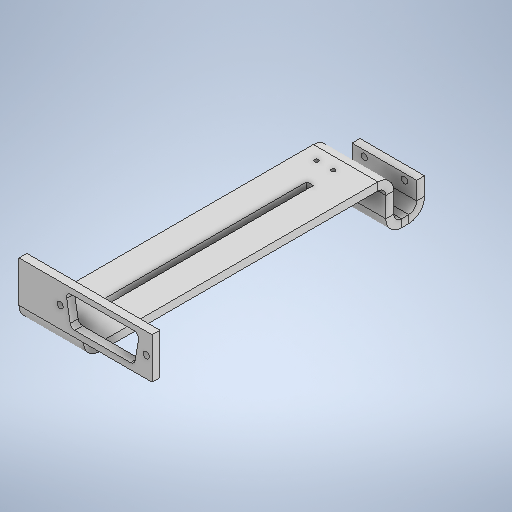
# Autodesk Inventor part: Blacha
Saved by Autodesk Inventor 2025.2 (Build 292293000, 293)
## iProperties
Created: 2025-04-10
Part Number: Blacha
Material: Generic
Document SubType Name: Sheet Metal
Designer: makst
Density: 1 g/cm^3
Sheet Metal Rule: Default
Appearance: Default
Author: makst
Autodesk Inventor part; units mm, degrees
ref_plane "YZ Plane" through (0, 0, 0) normal (1, 0, 0) x (0, 1, 0)
ref_plane "XZ Plane" through (0, 0, 0) normal (0, 1, 0) x (-1, 0, 0)
ref_plane "XY Plane" through (0, 0, 0) normal (0, 0, 1) x (1, 0, 0)
sketch "Sketch1" plane through (0, 0, 0) normal (0, 1, 0) x (-1, 0, 0)
  line L0 (0, 0) -> (0, -15)
  line L1 (0, -15) -> (25, -15)
  line L2 (25, -15) -> (25, 0)
  line L3 (25, 0) -> (0, 0)
  dimension "d0" = 15
  dimension "d2" = 25
  measures "d0" distance of L0.start L0.end
  measures "d2" distance of L0.end L1.end
extrude "Plate1" add sketch "Sketch1" along normal blind 3.048
sketch "Sketch2" plane through (-25, 0, -11.952) normal (0, 0, -1) x (-1, 0, 0)
  line L0 (-25, 0) -> (0, 0)
  line L1 (0, 0) -> (0, 23)
  line L2 (0, 23) -> (-25, 23)
  line L3 (-25, 23) -> (-25, 0)
  constraints: 6 end point, 1 horizontal, 1 perpendicular, 1 vertical
edge flange "Flange1" height 23 angle 90 thickness 3.048 bend radius 3.048 thickness toward (0, 0, -1) relief tear relief width 3.048 relief depth 1.524 edges at (-12.5, 3.048, -15) wall of the first edge with corners at (0, 0, -11.952) (-25, 0, -11.952) (-25, 23, -11.952) (0, 23, -11.952)
bend "Bend1"
corner "Corner1"
sketch "Sketch4" plane through (0, 23, -15) normal (0, 0, -1) x (-1, 0, 0)
  line L0 (0, -16.904) -> (25, -16.904) projected
  line L1 (0, -16.904) -> (0, 0) projected
  line L2 (25, 0) -> (25, -16.904) projected
  line L3 (12.5, -16.904) -> (12.5, -5.7009) construction
  point P0 (0, -23)
  point P1 (4.73, -12.2858)
  point P2 (20.27, -12.2858)
  dimension "d14" = 7.77
  dimension "d15" = 7.77
  constraints: 2 end point, 1 midpoint, 1 vertical
  measures "d14" distance from line of L3 point (4.73, -12.286)
  measures "d15" distance from line of point (20.27, -12.286) L3
hole "Hole1" at (-4.73, 10.7142, -15) at (-20.27, 10.7142, -15) direction (0, 0, 1) diameter 2.459 depth 4 thread size "M3x0.5" class "6H" standard "ISO Metric profile"
sketch "Sketch5" plane through (-25, 23, -11.952) normal (0, 0, 1) x (1, 0, 0)
  line L0 (25, 0) -> (0, 0) projected
  line L1 (0, 0) -> (0, -10)
  line L2 (0, 0) -> (0, -16.904) projected
  line L3 (0, -10) -> (25, -10)
  line L4 (25, -16.904) -> (25, 0) projected
  line L5 (25, 0) -> (0, 0)
  point P0 (25, -23)
  dimension "d23" = 10
  constraints: 6 end point, 2 point on line, 1 parallel, 1 perpendicular
  measures "d23" distance of L0.end L1.end
extrude "Extrusion1" cut sketch "Sketch5" against normal blind 10
sketch "Sketch7" plane through (0, 0, -3.048) normal (0, 0, 1) x (1, 0, 0)
  line L0 (-25, 0) -> (0, 0)
  line L1 (0, 0) -> (0, 20)
  line L2 (0, 20) -> (-25, 20)
  line L3 (-25, 20) -> (-25, 0)
  constraints: 6 end point, 1 horizontal, 1 perpendicular, 1 vertical
edge flange "Flange2" height 20 angle 90 thickness 3.048 bend radius 3.048 thickness toward (0, 0, 1) relief tear relief width 3.048 relief depth 1.524 edges at (-12.5, 3.048, 0) wall of the first edge with corners at (-25, 0, -3.048) (0, 0, -3.048) (0, 20, -3.048) (-25, 20, -3.048)
bend "Bend2"
corner "Corner2"
sketch "Sketch8" plane through (-25, 16.952, -3.048) normal (0, 1, 0) x (-1, 0, 0)
  line L0 (-25, 0) -> (0, 0)
  line L1 (0, 0) -> (0, 120)
  line L2 (0, 120) -> (-25, 120)
  line L3 (-25, 120) -> (-25, 0)
  constraints: 6 end point, 1 horizontal, 1 perpendicular, 1 vertical
edge flange "Flange3" height 120 angle 90 thickness 3.048 bend radius 3.048 thickness toward (0, 1, 0) relief tear relief width 3.048 relief depth 1.524 edges at (-12.5, 20, 0) wall of the first edge with corners at (0, 16.952, -3.048) (-25, 16.952, -3.048) (-25, 16.952, 116.952) (0, 16.952, 116.952)
bend "Bend3"
corner "Corner3"
sketch "Sketch9" plane through (-25, 20, 116.952) normal (0, 1, 0) x (1, 0, 0)
  line L0 (25, 113.904) -> (25, 0) projected
  line L1 (0, 0) -> (0, 113.904) projected
  line L2 (25, 0) -> (0, 0) projected
  line L3 (25, 113.904) -> (0, 113.904) projected
  line L4 (0, 113.904) -> (25, 113.904) projected
  line L5 (11.25, 18.904) -> (11.25, 98.904)
  line L6 (13.75, 18.904) -> (13.75, 98.904)
  line L7 (12.5, 98.904) -> (12.5, 97.654)
  line L8 (11.25, 18.904) -> (11.25, 17.654)
  line L9 (11.25, 17.654) -> (13.75, 17.654)
  line L10 (13.75, 17.654) -> (13.75, 18.904)
  line L11 (11.25, 98.904) -> (11.25, 100.154)
  line L12 (11.25, 100.154) -> (13.75, 100.154)
  line L13 (13.75, 100.154) -> (13.75, 98.904)
  point P0 (25, 116.952)
  dimension "d46" = 15
  constraints: 18 end point, 3 perpendicular, 1 coincident, 1 point on line, 1 vertical
  measures "d46" distance from line of L3 point (12.5, 98.904)
extrude "Extrusion2" cut sketch "Sketch9" against normal blind 10 contours L5 L11 L12 L13 L6 L10 L9 L8
sketch "Sketch10" plane through (-25, 16.952, 116.952) normal (0, -1, 0) x (1, 0, 0)
  line L0 (0, -113.904) -> (0, 0) projected
  line L1 (13.75, -100.154) -> (11.25, -100.154) projected
  line L2 (13.75, -100.154) -> (13.75, -58.904) construction
  line L3 (13.75, -100.154) -> (13.75, -17.654) projected
  line L4 (13.75, -58.904) -> (32.0073, -58.904) construction
  point P0 (25, -116.952)
  point P1 (12.5, -109.154)
  point P2 (6, -109.154)
  point P3 (12.5, -8.654)
  point P4 (6, -8.654)
  dimension "d52" = 12.5
  dimension "d53" = 9
  dimension "d54" = 6.5
  dimension "d62" = 41.25
  constraints: 4 end point, 2 symmetric about line, 1 horizontal, 1 midpoint
  measures "d52" distance from line of point (12.5, -109.154) L0
  measures "d53" distance from line of point (12.5, -109.154) L1
  measures "d54" distance of point (6, -109.154) point (12.5, -109.154)
  measures "d62" distance of L1.start L2.end
hole "Hole2" at (-12.5, 16.952, 7.798) at (-19, 16.952, 7.798) at (-19, 16.952, 108.298) at (-12.5, 16.952, 108.298) direction (0, 1, 0) diameter 1.567 depth 6.3 thread size "M2x0.4" class "6H" standard "ISO Metric profile"
sketch "Sketch12" plane through (0, 16.952, 113.904) normal (0, 0, 1) x (1, 0, 0)
  line L0 (-25, 0) -> (0, 0)
  line L1 (0, 0) -> (0, 22)
  line L2 (0, 22) -> (-25, 22)
  line L3 (-25, 22) -> (-25, 0)
  constraints: 6 end point, 1 horizontal, 1 perpendicular, 1 vertical
edge flange "Flange5" height 22 angle 90 thickness 3.048 bend radius 3.048 thickness toward (0, 0, 1) relief tear relief width 3.048 relief depth 1.524 edges at (-12.5, 20, 116.952) wall of the first edge with corners at (-25, 16.952, 113.904) (0, 16.952, 113.904) (0, 38.952, 113.904) (-25, 38.952, 113.904)
bend "Bend5"
corner "Corner5"
sketch "Sketch14" plane through (0, 38.952, 116.952) normal (1, 0, 0) x (0, 0, -1)
  line L0 (3.048, 0) -> (0, 0) projected
  line L1 (3.048, 0) -> (0, 0)
  line L2 (0, -15.904) -> (0, 0) projected
  line L3 (0, 0) -> (0, -15.904)
  line L4 (0, -15.904) -> (3.048, -15.904)
  line L5 (3.048, -15.904) -> (3.048, 0)
  point P0 (116.952, -38.952)
  constraints: 8 end point, 2 collinear, 2 perpendicular
extrude "Extrusion3" add sketch "Sketch14" along normal blind 26.5
sketch "Sketch15" plane through (-25, 23.048, 116.952) normal (0, 0, 1) x (1, 0, 0)
  line L0 (41.5674, 1.7998) -> (5.5756, 1.7998) projected
  arc A0 (41.5674, 1.7998) -> (43.1422, 3.3746) centre (41.5674, 3.3746) ccw projected
  line L1 (43.1422, 12.8234) -> (43.1422, 3.3746) projected
  arc A1 (43.1422, 12.8234) -> (41.5674, 14.3982) centre (41.5674, 12.8234) ccw projected
  line L2 (5.5756, 14.3982) -> (41.5674, 14.3982) projected
  arc A2 (5.5756, 14.3982) -> (4.0008, 12.8234) centre (5.5756, 12.8234) ccw projected
  line L3 (4.0008, 3.3746) -> (4.0008, 12.8234) projected
  arc A3 (4.0008, 3.3746) -> (5.5756, 1.7998) centre (5.5756, 3.3746) ccw projected
  circle A4 centre (6.9091, 8.099) radius 1.524 projected
  circle A5 centre (40.2339, 8.099) radius 1.524 projected
  circle A6 centre (40.2339, 8.099) radius 1.524
  line L4 (0, 0) -> (0, 15.904) projected
  point P0 (25, -23.048)
  point P1 (15.9091, 8.099)
  point P2 (49.2339, 7.9363)
  dimension "d98" = 9
  dimension "d99" = 9
  constraints: 2 coincident, 1 centre point, 1 concentric
  measures "d98" horizontal distance of point (49.234, 7.936) A5.centre
  measures "d99" distance of A4.centre point (15.909, 8.099)
hole "Hole3" at (15.2339, 31.147, 116.952) at (24.2339, 30.9843, 116.952) at (-9.0909, 31.147, 116.952) direction (0, 0, -1) diameter 2.459 depth 8.8 thread size "M3x0.5" class "6H" standard "ISO Metric profile"
sketch "Sketch16" plane through (-25, 23.048, 116.952) normal (0, 0, 1) x (1, 0, 0)
  line L0 (32.8661, 4.1493) -> (14.2769, 4.1493) projected
  arc A0 (32.8661, 4.1493) -> (35.3675, 6.2482) centre (32.8661, 6.6893) ccw projected
  line L1 (35.8646, 9.0676) -> (35.3675, 6.2482) projected
  arc A1 (35.8646, 9.0676) -> (33.3632, 12.0487) centre (33.3632, 9.5087) ccw projected
  line L2 (13.7798, 12.0487) -> (33.3632, 12.0487) projected
  line L3 (35.7475, 13.5981) -> (11.3955, 13.5981) projected
  arc A2 (37.2984, 11.7498) -> (35.7475, 13.5981) centre (35.7475, 12.0233) ccw projected
  line L4 (35.9145, 3.9012) -> (37.2984, 11.7498) projected
  arc A3 (34.3636, 2.5999) -> (35.9145, 3.9012) centre (34.3636, 4.1747) ccw projected
  line L5 (12.7794, 2.5999) -> (34.3636, 2.5999) projected
  arc A4 (11.2285, 3.9012) -> (12.7794, 2.5999) centre (12.7794, 4.1747) ccw projected
  line L6 (9.8691, 11.6109) -> (11.2285, 3.9012) projected
  arc A5 (11.3955, 13.5981) -> (9.8691, 11.6109) centre (11.3889, 12.0233) ccw projected
  line L7 (43.1636, 2.3999) -> (21.5794, 2.3999)
  arc A6 (19.8316, 3.8665) -> (21.5794, 2.3999) centre (21.5794, 4.1747) ccw
  line L8 (19.8316, 3.8665) -> (18.4737, 11.5675)
  arc A7 (20.1959, 13.7981) -> (18.4737, 11.5675) centre (20.1889, 12.0233) ccw
  line L9 (20.1959, 13.7981) -> (44.5475, 13.7981)
  arc A8 (46.2954, 11.7151) -> (44.5475, 13.7981) centre (44.5475, 12.0233) ccw
  line L10 (46.2954, 11.7151) -> (44.9115, 3.8665)
  arc A9 (43.1636, 2.3999) -> (44.9115, 3.8665) centre (43.1636, 4.1747) ccw
  point P0 (25, -23.048)
  point P1 (34.3636, 2.5999)
  point P2 (34.3636, 2.3999)
  point P3 (44.1636, 2.3999)
  point P4 (20.7609, 2.5999)
  point P5 (19.3704, 13.5981)
  point P6 (43.1636, 2.3999)
  point P7 (18.4143, 12.0487)
  point P8 (19.7817, 4.1493)
  dimension "d94" = 9
  constraints: 8 end point, 8 point on circle, 4 centre point
extrude "Extrusion4" cut sketch "Sketch16" against normal blind 22 contours A0 L1 A1 L2 A7 L3 A2 L4 A3 L5 A6 L8 L0 | L0 L8 A7 L2 A1 L1 A0 | L5 A3 L4 A2 L3 A7 L9 A8 L10 A9 L7 A6
equation "\"d3\" = Thickness"
equation "\"d4\" = BendReliefWidth"
equation "\"d5\" = BendReliefDepth"
equation "\"d6\" = MinimumRemnant"
equation "\"d7\" = TransitionRadius"
equation "\"d10\" = BendRadius"
equation "\"d11\" = CornerReliefSize"
equation "\"d12\" = GapSize"
equation "\"d13\" = JacobiRadiusSize"
equation "\"d26\" = BendReliefWidth"
equation "\"d27\" = BendReliefDepth"
equation "\"d28\" = MinimumRemnant"
equation "\"d29\" = TransitionRadius"
equation "\"d32\" = BendRadius"
equation "\"d33\" = CornerReliefSize"
equation "\"d34\" = GapSize"
equation "\"d35\" = JacobiRadiusSize"
equation "\"d36\" = BendReliefWidth"
equation "\"d37\" = BendReliefDepth"
equation "\"d38\" = MinimumRemnant"
equation "\"d39\" = TransitionRadius"
equation "\"d42\" = BendRadius"
equation "\"d43\" = CornerReliefSize"
equation "\"d44\" = GapSize"
equation "\"d45\" = JacobiRadiusSize"
equation "\"d73\" = BendReliefWidth"
equation "\"d74\" = BendReliefDepth"
equation "\"d75\" = MinimumRemnant"
equation "\"d76\" = TransitionRadius"
equation "\"d79\" = BendRadius"
equation "\"d80\" = CornerReliefSize"
equation "\"d81\" = GapSize"
equation "\"d82\" = JacobiRadiusSize"
equation "\"BendRadius\" = Thickness"
equation "\"BendReliefWidth\" = Thickness"
equation "\"BendReliefDepth\" = 0.5 * Thickness"
equation "\"CornerReliefSize\" = 4 * Thickness"
equation "\"MinimumRemnant\" = 2 * Thickness"
equation "\"TransitionRadius\" = BendRadius"
equation "\"JacobiRadiusSize\" = BendRadius"
equation "\"GapSize\" = Thickness"
equation "\"Thickness\" = 3.048"
body "Solid1"
